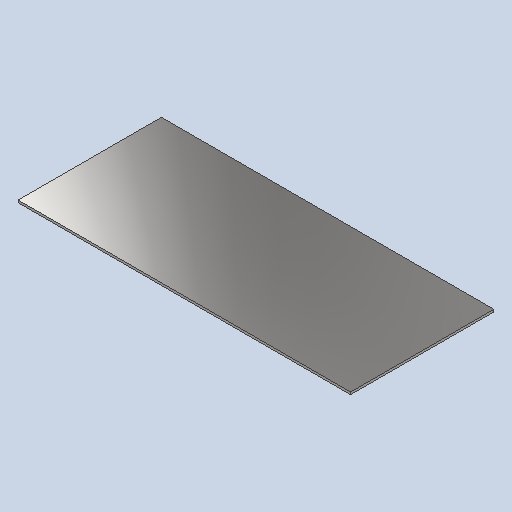
# Autodesk Inventor part: RDS-1402 Motor Plate
Saved by Autodesk Inventor 2026.2 (Build 302298000, 298)
## iProperties
Created: 2026-10-18
Part Number: RDS-1402 Motor Plate
Material: Stainless Steel, Austenitic
Description: Motor plate, AISI 304 4 mm
Document SubType Name: Sheet Metal
Designer: admin
Stock Number: Плита под мотор-редуктор (как FL3.6.2 Motor pillar)
Density: 8 g/cm^3
Flat Pattern Width: 25 cm
Flat Pattern Length: 58 cm
Flat Pattern Area: 1450 cm^2
Sheet Metal Rule: Default
Sheet Metal Width: 250,000 mm
Sheet Metal Length: 580,000 mm
Sheet Metal Area: 145000,000 mm^2
Appearance: Semi-Polished
Author: admin
Autodesk Inventor part; units mm, degrees
ref_plane "YZ Plane" through (0, 0, 0) normal (1, 0, 0) x (0, 1, 0)
ref_plane "XZ Plane" through (0, 0, 0) normal (0, 1, 0) x (-1, 0, 0)
ref_plane "XY Plane" through (0, 0, 0) normal (0, 0, 1) x (1, 0, 0)
sketch "Sketch1" plane through (0, 0, 0) normal (0, 1, 0) x (-1, 0, 0)
  line L0 (290, -125) -> (-290, -125)
  line L1 (-290, -125) -> (-290, 125)
  line L2 (-290, 125) -> (290, 125)
  line L3 (290, 125) -> (290, -125)
  dimension "d0" = 580
  dimension "d1" = 250
  measures "d0" distance of L0.start L0.end
  measures "d1" distance of L0.end L1.end
extrude "Plate1" add sketch "Sketch1" along normal blind 4
equation "\"d0\" = Plate1402_Width"
equation "\"d1\" = Plate1402_Length"
equation "\"d2\" = Thickness"
equation "\"BendRadius\" = Thickness"
equation "\"BendReliefWidth\" = Thickness"
equation "\"BendReliefDepth\" = 0.5 * Thickness"
equation "\"CornerReliefSize\" = 4 * Thickness"
equation "\"MinimumRemnant\" = 2 * Thickness"
equation "\"TransitionRadius\" = BendRadius"
equation "\"JacobiRadiusSize\" = BendRadius"
equation "\"GapSize\" = Thickness"
equation "\"Plate1402_Width\" = 580"
equation "\"Plate1402_Length\" = 250"
equation "\"Thickness\" = 4"
body "Solid1"
